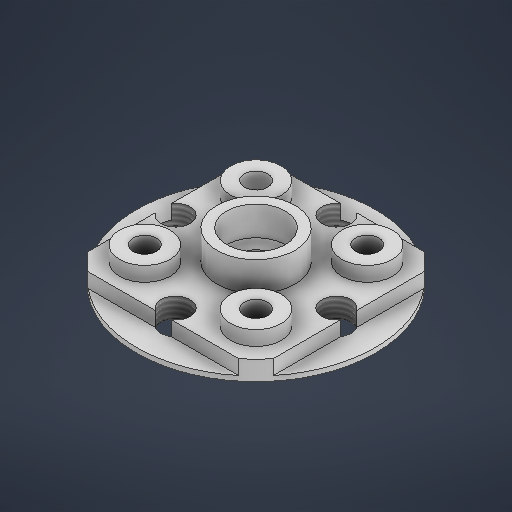
# Autodesk Inventor part: Alu_Kupplung_disc
Saved by Autodesk Inventor 2027.2 (Build 312334000, 334)
## iProperties
Created: 2026-11-16
Part Number: Alu_Kupplung_disc
Material: Generisch
Document SubType Name: Modeling
Designer: matej
Density: 1 g/cm^3
Appearance: Vorgabe
Author: matej
Autodesk Inventor part; units mm, degrees
ref_plane "YZ Plane" through (0, 0, 0) normal (1, 0, 0) x (0, 1, 0)
ref_plane "XZ Plane" through (0, 0, 0) normal (0, 1, 0) x (-1, 0, 0)
ref_plane "XY Plane" through (0, 0, 0) normal (0, 0, 1) x (1, 0, 0)
sketch "Skizze1" plane through (0, 0, 0) normal (0, 0, 1) x (1, 0, 0)
  circle A0 centre (0, 0) radius 12.25
  line L0 (-8.25, -8.25) -> (8.25, 8.25) construction
  line L1 (8.25, -6.5) -> (-8.25, 6.5) construction
  circle A1 centre (-8.25, 0) radius 1.5
  circle A2 centre (0, -8.25) radius 1.5
  circle A3 centre (8.25, 0) radius 1.5
  circle A4 centre (0, 8.25) radius 1.5
  circle A5 centre (0, 0) radius 1.5
  dimension "d14" = 3
  dimension "d17" = 360
  dimension "d19" = 3
  constraints: 6 centre point, 4 end point, 1 coincident, 9 other
  measures "d14" diameter of A1
  measures "d19" diameter of A5
extrude "Extrusion1" add sketch "Skizze1" along normal blind 2
sketch "Skizze2" plane through (0, 0, 2) normal (0, 0, 1) x (1, 0, 0)
  circle A0 centre (0, 0) radius 1.5 projected
  circle A1 centre (0, 0) radius 4
  circle A2 centre (0, 0) radius 3
  dimension "d22" = 8
  dimension "d23" = 6
  constraints: 2 centre point, 2 coincident
  measures "d22" diameter of A1
  measures "d23" diameter of A2
extrude "Extrusion2" add sketch "Skizze2" along normal blind 3 contours A1
thread "Gewinde1" size "M3x0.5" class "6H" standard "ANSI Metric M Profile" full length
thread "Gewinde2" size "M3x0.5" class "6H" standard "ANSI Metric M Profile" full length
thread "Gewinde3" size "M3x0.5" class "6H" standard "ANSI Metric M Profile" full length
thread "Gewinde4" size "M3x0.5" class "6H" standard "ANSI Metric M Profile" full length
sketch "Skizze3" plane through (0, 0, 2) normal (0, 0, 1) x (1, 0, 0)
  circle A0 centre (0, 0) radius 12.25 projected
  line L0 (0, 12.25) -> (0, -10.05)
  circle A1 centre (0, 0) radius 1.5 projected
  line L1 (-6.6716, -5.9716) -> (1.9284, -5.9716) construction
  circle A2 centre (0, 0) radius 4 projected
  circle A3 centre (0, 0) radius 14
  line L2 (-5.7, -5.7) -> (5.7, -5.7)
  line L3 (5.7, -5.7) -> (5.7, 5.7)
  line L4 (5.7, 5.7) -> (-5.7, 5.7)
  line L5 (-5.7, 5.7) -> (-5.7, -5.7)
  line L6 (-5.7, -5.7) -> (5.7, 5.7) construction
  line L7 (5.7, -5.7) -> (-5.7, 5.7) construction
  circle A4 centre (-5.7, 5.7) radius 2.6
  circle A5 centre (0, 0) radius 3 projected
  line L8 (0, 0) -> (0, -10)
  line L9 (0, -10) -> (9.5, -10)
  line L10 (9.5, -10) -> (9.5, 9)
  line L11 (9.5, 9) -> (0, 9)
  line L12 (0, 9) -> (0, -10)
  line L13 (0, -10) -> (-9.5, -10)
  line L14 (-9.5, -10) -> (-9.5, 9)
  line L15 (-9.5, 9) -> (0, 9)
  circle A6 centre (5.7, 5.7) radius 2.6
  circle A7 centre (5.7, -5.7) radius 2.6
  circle A8 centre (-5.7, -5.7) radius 2.6
  circle A9 centre (-5.7, 5.7) radius 1.2
  circle A10 centre (-5.7, -5.7) radius 1.2
  circle A11 centre (5.7, -5.7) radius 1.2
  circle A12 centre (5.7, 5.7) radius 1.2
  dimension "d34" = 22.3
  dimension "d51" = 28
  dimension "d52" = 11.4
  dimension "d53" = 11.4
  dimension "d54" = 5.2
  dimension "d55" = 10
  dimension "d58" = 9.5
  dimension "d59" = 19
  dimension "d60" = 5.2
  dimension "d61" = 5.2
  dimension "d62" = 5.2
  dimension "d63" = 2.4
  dimension "d66" = 360
  constraints: 32 end point, 9 centre point, 6 coincident, 4 parallel, 3 horizontal, 2 midpoint, 2 perpendicular, 2 symmetric about line, 1 point on line, 1 vertical, 1 vertical alignment, 10 other
  measures "d34" distance of L0.start L0.end
  measures "d51" diameter of A3
  measures "d52" distance of L4.end L3.end
  measures "d53" distance of L3.end L2.end
  measures "d54" diameter of A4
  measures "d55" distance of L8.start L8.end
  measures "d58" distance of L11.end L10.end
  measures "d59" distance of L10.end L9.end
  measures "d60" diameter of A6
  measures "d61" diameter of A7
  measures "d62" diameter of A8
  measures "d63" diameter of A9
extrude "Extrusion3" cut sketch "Skizze3" against normal through all contours A12 L3 L4 | L4 L3 A12 | A9 L5 L4 | L4 L5 A9 | A10 L5 L2 | L2 L5 A10 | A11 L3 L2 | L2 L3 A11
sketch "Skizze4" plane through (0, 0, 2) normal (0, 0, 1) x (1, 0, 0)
  circle A0 centre (-5.7, 5.7) radius 1.2 projected
  circle A1 centre (-5.7, 5.7) radius 2.6
  circle A2 centre (-5.7, -5.7) radius 2.6
  circle A3 centre (5.7, -5.7) radius 2.6
  circle A4 centre (5.7, 5.7) radius 2.6
  circle A5 centre (-5.7, -5.7) radius 1.2
  circle A6 centre (5.7, -5.7) radius 1.2
  circle A7 centre (5.7, 5.7) radius 1.2
  point P0 (0, 0)
  dimension "d70" = 5.2
  dimension "d73" = 360
  constraints: 7 centre point, 4 coincident, 9 other
  measures "d70" diameter of A1
extrude "Extrusion4" add sketch "Skizze4" along normal blind 1.5
sketch "Skizze5" plane through (0, 0, 2) normal (0, 0, 1) x (1, 0, 0)
  line L0 (-9.5, -9.5) -> (9.5, -9.5)
  line L1 (9.5, -9.5) -> (9.5, 9.5)
  line L2 (9.5, 9.5) -> (-9.5, 9.5)
  line L3 (-9.5, 9.5) -> (-9.5, -9.5)
  line L4 (-9.5, -9.5) -> (9.5, 9.5) construction
  line L5 (9.5, -9.5) -> (-9.5, 9.5) construction
  circle A0 centre (0, 0) radius 3 projected
  circle A1 centre (0, 0) radius 12.25
  point P0 (7.7339, -9.5)
  point P1 (-7.7339, -9.5)
  point P2 (9.5, -7.7339)
  point P3 (9.5, 7.7339)
  point P4 (-7.7339, 9.5)
  point P5 (7.7339, 9.5)
  point P6 (-9.5, -7.7339)
  point P7 (-9.5, 7.7339)
  dimension "d77" = 19
  dimension "d78" = 19
  constraints: 12 end point, 2 midpoint, 2 parallel, 1 centre point, 1 coincident, 1 horizontal, 1 perpendicular
  measures "d77" distance of L2.end L1.end
  measures "d78" distance of L1.end L0.end
extrude "Extrusion5" cut sketch "Skizze5" against normal blind 1.5 contours L0 A1 | A1 L3 | L1 A1 | A1 L2
